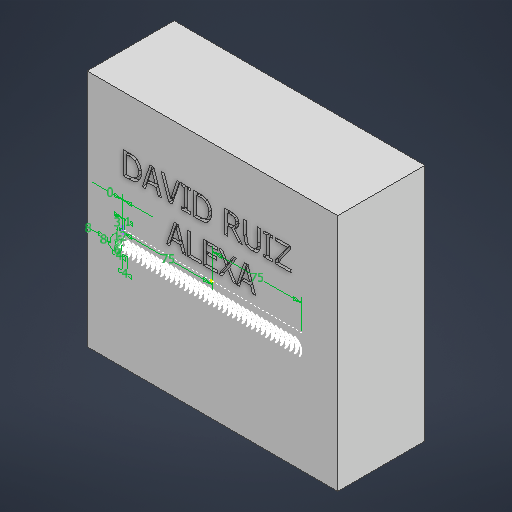
# Autodesk Inventor part: Trayectorias
Saved by Autodesk Inventor 2027.1 (Build 311270010, 270A)
## iProperties
Created: 2026-10-04
Part Number: Trayectorias
Material: Genérico
Document SubType Name: Modeling
Designer: felip
Density: 1 g/cm^3
Appearance: Valor por defecto
Author: felip
Autodesk Inventor part; units mm, degrees
ref_plane "YZ Plane" through (0, 0, 0) normal (1, 0, 0) x (0, 1, 0)
ref_plane "XZ Plane" through (0, 0, 0) normal (0, 1, 0) x (-1, 0, 0)
ref_plane "XY Plane" through (0, 0, 0) normal (0, 0, 1) x (1, 0, 0)
sketch "Boceto1" plane through (0, 0, 0) normal (0, 0, 1) x (1, 0, 0)
  line L0 (-105, 100) -> (105, 100)
  line L1 (105, 100) -> (105, -100)
  line L2 (105, -100) -> (-105, -100)
  line L3 (-105, -100) -> (-105, 100)
  line L4 (-105, 100) -> (105, -100) construction
  line L5 (105, 100) -> (-105, -100) construction
  point P0 (0, 0)
  dimension "d0" = 210
  dimension "d1" = 200
  constraints: 12 end point, 2 midpoint, 2 parallel, 1 horizontal, 1 perpendicular
  measures "d0" distance of L1.end L2.end
  measures "d1" distance of L0.end L1.end
extrude "Extrusión1" add sketch "Boceto1" along normal mid plane 73
sketch "Boceto2" plane through (0, 0, 36.5) normal (0, 0, 1) x (1, 0, 0)
  line L0 (-80.8572, 56.5825) -> (70.8243, 56.5825) construction
  line L1 (70.8243, 56.5825) -> (70.8243, 9.2236) construction
  line L2 (70.8243, 9.2236) -> (-80.8572, 9.2236) construction
  line L3 (-80.8572, 9.2236) -> (-80.8572, 56.5825) construction
  spline S0 degree 2 poles (-59.4185, 48.5703) (-59.4185, 45.9613) (-61.5335, 41.7623) (-63.3088, 40.589) knots 0 0 0 1 2 2 2
  spline S1 degree 2 poles (-63.3088, 40.589) (-64.76, 39.6782) (-67.7394, 39.0607) (-70.0551, 39.0607) knots 0 0 0 1 2 2 2
  line L4 (-70.0551, 39.0607) -> (-74.4393, 39.0607)
  line L5 (-74.4393, 39.0607) -> (-74.4393, 58.1107)
  line L6 (-74.4393, 58.1107) -> (-70.1014, 58.1107)
  spline S2 degree 2 poles (-70.1014, 58.1107) (-67.4152, 58.1107) (-64.3586, 57.308) (-63.2779, 56.5978) knots 0 0 0 1 2 2 2
  spline S3 degree 2 poles (-63.2779, 56.5978) (-61.4409, 55.3783) (-59.4185, 51.349) (-59.4185, 48.5703) knots 0 0 0 1 2 2 2
  spline S4 degree 2 poles (-62.0584, 48.6011) (-62.0584, 50.7933) (-63.5095, 53.8962) (-64.9452, 54.7762) knots 0 0 0 1 2 2 2
  spline S5 degree 2 poles (-64.9452, 54.7762) (-65.9641, 55.3783) (-68.2643, 55.9186) (-69.9779, 55.9186) knots 0 0 0 1 2 2 2
  line L7 (-69.9779, 55.9186) -> (-71.9076, 55.9186)
  line L8 (-71.9076, 55.9186) -> (-71.9076, 41.2528)
  line L9 (-71.9076, 41.2528) -> (-69.9779, 41.2528)
  spline S6 degree 2 poles (-69.9779, 41.2528) (-68.2952, 41.2528) (-65.748, 41.7932) (-64.7136, 42.5187) knots 0 0 0 1 2 2 2
  spline S7 degree 2 poles (-64.7136, 42.5187) (-63.386, 43.4141) (-62.0584, 46.3781) (-62.0584, 48.6011) knots 0 0 0 1 2 2 2
  line L10 (-58.7239, 39.0607) -> (-52.3018, 58.1107)
  line L11 (-52.3018, 58.1107) -> (-49.1834, 58.1107)
  line L12 (-49.1834, 58.1107) -> (-42.7614, 39.0607)
  line L13 (-42.7614, 39.0607) -> (-45.4321, 39.0607)
  line L14 (-45.4321, 39.0607) -> (-47.1611, 44.3867)
  line L15 (-47.1611, 44.3867) -> (-54.4322, 44.3867)
  line L16 (-54.4322, 44.3867) -> (-56.1612, 39.0607)
  line L17 (-56.1612, 39.0607) -> (-58.7239, 39.0607)
  line L18 (-47.8558, 46.5479) -> (-50.8044, 55.5172)
  line L19 (-50.8044, 55.5172) -> (-53.7375, 46.5479)
  line L20 (-53.7375, 46.5479) -> (-47.8558, 46.5479)
  line L21 (-27.1385, 58.1107) -> (-33.6995, 39.0607)
  line L22 (-33.6995, 39.0607) -> (-36.432, 39.0607)
  line L23 (-36.432, 39.0607) -> (-42.9929, 58.1107)
  line L24 (-42.9929, 58.1107) -> (-40.2759, 58.1107)
  line L25 (-40.2759, 58.1107) -> (-34.9963, 42.2872)
  line L26 (-34.9963, 42.2872) -> (-29.7166, 58.1107)
  line L27 (-29.7166, 58.1107) -> (-27.1385, 58.1107)
  line L28 (-18.6787, 39.0607) -> (-26.0579, 39.0607)
  line L29 (-26.0579, 39.0607) -> (-26.0579, 41.0058)
  line L30 (-26.0579, 41.0058) -> (-23.6342, 41.0058)
  line L31 (-23.6342, 41.0058) -> (-23.6342, 56.1656)
  line L32 (-23.6342, 56.1656) -> (-26.0579, 56.1656)
  line L33 (-26.0579, 56.1656) -> (-26.0579, 58.1107)
  line L34 (-26.0579, 58.1107) -> (-18.6787, 58.1107)
  line L35 (-18.6787, 58.1107) -> (-18.6787, 56.1656)
  line L36 (-18.6787, 56.1656) -> (-21.1024, 56.1656)
  line L37 (-21.1024, 56.1656) -> (-21.1024, 41.0058)
  line L38 (-21.1024, 41.0058) -> (-18.6787, 41.0058)
  line L39 (-18.6787, 41.0058) -> (-18.6787, 39.0607)
  spline S8 degree 2 poles (-0.5241, 48.5703) (-0.5241, 45.9613) (-2.6391, 41.7623) (-4.4144, 40.589) knots 0 0 0 1 2 2 2
  spline S9 degree 2 poles (-4.4144, 40.589) (-5.8655, 39.6782) (-8.845, 39.0607) (-11.1606, 39.0607) knots 0 0 0 1 2 2 2
  line L40 (-11.1606, 39.0607) -> (-15.5449, 39.0607)
  line L41 (-15.5449, 39.0607) -> (-15.5449, 58.1107)
  line L42 (-15.5449, 58.1107) -> (-11.2069, 58.1107)
  spline S10 degree 2 poles (-11.2069, 58.1107) (-8.5208, 58.1107) (-5.4641, 57.308) (-4.3835, 56.5978) knots 0 0 0 1 2 2 2
  spline S11 degree 2 poles (-4.3835, 56.5978) (-2.5464, 55.3783) (-0.5241, 51.349) (-0.5241, 48.5703) knots 0 0 0 1 2 2 2
  spline S12 degree 2 poles (-3.1639, 48.6011) (-3.1639, 50.7933) (-4.6151, 53.8962) (-6.0508, 54.7762) knots 0 0 0 1 2 2 2
  spline S13 degree 2 poles (-6.0508, 54.7762) (-7.0696, 55.3783) (-9.3698, 55.9186) (-11.0834, 55.9186) knots 0 0 0 1 2 2 2
  line L43 (-11.0834, 55.9186) -> (-13.0131, 55.9186)
  line L44 (-13.0131, 55.9186) -> (-13.0131, 41.2528)
  line L45 (-13.0131, 41.2528) -> (-11.0834, 41.2528)
  spline S14 degree 2 poles (-11.0834, 41.2528) (-9.4007, 41.2528) (-6.8535, 41.7932) (-5.8192, 42.5187) knots 0 0 0 1 2 2 2
  spline S15 degree 2 poles (-5.8192, 42.5187) (-4.4916, 43.4141) (-3.1639, 46.3781) (-3.1639, 48.6011) knots 0 0 0 1 2 2 2
  line L46 (25.1486, 39.0607) -> (21.8604, 39.0607)
  line L47 (21.8604, 39.0607) -> (15.8398, 46.6406)
  line L48 (15.8398, 46.6406) -> (12.9375, 46.6406)
  line L49 (12.9375, 46.6406) -> (12.9375, 39.0607)
  line L50 (12.9375, 39.0607) -> (10.4057, 39.0607)
  line L51 (10.4057, 39.0607) -> (10.4057, 58.1107)
  line L52 (10.4057, 58.1107) -> (15.3149, 58.1107)
  spline S16 degree 2 poles (15.3149, 58.1107) (16.9513, 58.1107) (19.1588, 57.7556) (20.1623, 57.1073) knots 0 0 0 1 2 2 2
  spline S17 degree 2 poles (20.1623, 57.1073) (21.1657, 56.4589) (22.3235, 54.4366) (22.3235, 52.9391) knots 0 0 0 1 2 2 2
  spline S18 degree 2 poles (22.3235, 52.9391) (22.3235, 50.855) (20.1932, 48.03) (18.3715, 47.3507) knots 0 0 0 1 2 2 2
  line L53 (18.3715, 47.3507) -> (25.1486, 39.0607)
  spline S19 degree 2 poles (19.6837, 52.7384) (19.6837, 53.5721) (19.0971, 54.8534) (18.4796, 55.2702) knots 0 0 0 1 2 2 2
  spline S20 degree 2 poles (18.4796, 55.2702) (17.9393, 55.6253) (16.5036, 55.9186) (15.4538, 55.9186) knots 0 0 0 1 2 2 2
  line L54 (15.4538, 55.9186) -> (12.9375, 55.9186)
  line L55 (12.9375, 55.9186) -> (12.9375, 48.7555)
  line L56 (12.9375, 48.7555) -> (15.1605, 48.7555)
  spline S21 degree 2 poles (15.1605, 48.7555) (16.2566, 48.7555) (18.001, 49.1415) (18.6031, 49.7435) knots 0 0 0 1 2 2 2
  spline S22 degree 2 poles (18.6031, 49.7435) (19.1588, 50.2684) (19.6837, 51.7504) (19.6837, 52.7384) knots 0 0 0 1 2 2 2
  spline S23 degree 2 poles (33.3151, 38.6593) (31.6324, 38.6593) (29.1315, 39.5393) (28.2516, 40.4192) knots 0 0 0 1 2 2 2
  spline S24 degree 2 poles (28.2516, 40.4192) (27.2481, 41.4072) (26.43, 44.186) (26.43, 46.2238) knots 0 0 0 1 2 2 2
  line L57 (26.43, 46.2238) -> (26.43, 58.1107)
  line L58 (26.43, 58.1107) -> (28.9617, 58.1107)
  line L59 (28.9617, 58.1107) -> (28.9617, 46.2238)
  spline S25 degree 2 poles (28.9617, 46.2238) (28.9617, 44.8961) (29.3013, 43.1054) (29.7799, 42.3798) knots 0 0 0 1 2 2 2
  spline S26 degree 2 poles (29.7799, 42.3798) (30.2894, 41.6079) (32.0492, 40.8206) (33.3151, 40.8206) knots 0 0 0 1 2 2 2
  spline S27 degree 2 poles (33.3151, 40.8206) (34.5038, 40.8206) (36.3563, 41.6079) (36.8658, 42.3798) knots 0 0 0 1 2 2 2
  spline S28 degree 2 poles (36.8658, 42.3798) (37.3443, 43.1054) (37.684, 44.8807) (37.684, 46.162) knots 0 0 0 1 2 2 2
  line L60 (37.684, 46.162) -> (37.684, 58.1107)
  line L61 (37.684, 58.1107) -> (40.2157, 58.1107)
  line L62 (40.2157, 58.1107) -> (40.2157, 46.2238)
  spline S29 degree 2 poles (40.2157, 46.2238) (40.2157, 44.2323) (39.413, 41.3918) (38.3941, 40.4192) knots 0 0 0 1 2 2 2
  spline S30 degree 2 poles (38.3941, 40.4192) (37.4833, 39.5238) (35.075, 38.6593) (33.3151, 38.6593) knots 0 0 0 1 2 2 2
  line L63 (50.4817, 39.0607) -> (43.1026, 39.0607)
  line L64 (43.1026, 39.0607) -> (43.1026, 41.0058)
  line L65 (43.1026, 41.0058) -> (45.5263, 41.0058)
  line L66 (45.5263, 41.0058) -> (45.5263, 56.1656)
  line L67 (45.5263, 56.1656) -> (43.1026, 56.1656)
  line L68 (43.1026, 56.1656) -> (43.1026, 58.1107)
  line L69 (43.1026, 58.1107) -> (50.4817, 58.1107)
  line L70 (50.4817, 58.1107) -> (50.4817, 56.1656)
  line L71 (50.4817, 56.1656) -> (48.058, 56.1656)
  line L72 (48.058, 56.1656) -> (48.058, 41.0058)
  line L73 (48.058, 41.0058) -> (50.4817, 41.0058)
  line L74 (50.4817, 41.0058) -> (50.4817, 39.0607)
  line L75 (65.765, 39.0607) -> (52.4577, 39.0607)
  line L76 (52.4577, 39.0607) -> (52.4577, 41.4227)
  line L77 (52.4577, 41.4227) -> (62.6466, 55.8568)
  line L78 (62.6466, 55.8568) -> (52.9209, 55.8568)
  line L79 (52.9209, 55.8568) -> (52.9209, 58.1107)
  line L80 (52.9209, 58.1107) -> (65.5025, 58.1107)
  line L81 (65.5025, 58.1107) -> (65.5025, 55.8259)
  line L82 (65.5025, 55.8259) -> (55.2056, 41.3146)
  line L83 (55.2056, 41.3146) -> (65.765, 41.3146)
  line L84 (65.765, 41.3146) -> (65.765, 39.0607)
  line L85 (-38.3539, 7.6954) -> (-31.9319, 26.7454)
  line L86 (-31.9319, 26.7454) -> (-28.8135, 26.7454)
  line L87 (-28.8135, 26.7454) -> (-22.3915, 7.6954)
  line L88 (-22.3915, 7.6954) -> (-25.0622, 7.6954)
  line L89 (-25.0622, 7.6954) -> (-26.7912, 13.0214)
  line L90 (-26.7912, 13.0214) -> (-34.0623, 13.0214)
  line L91 (-34.0623, 13.0214) -> (-35.7913, 7.6954)
  line L92 (-35.7913, 7.6954) -> (-38.3539, 7.6954)
  line L93 (-27.4859, 15.1826) -> (-30.4345, 24.1519)
  line L94 (-30.4345, 24.1519) -> (-33.3676, 15.1826)
  line L95 (-33.3676, 15.1826) -> (-27.4859, 15.1826)
  line L96 (-9.5474, 7.6954) -> (-20.5853, 7.6954)
  line L97 (-20.5853, 7.6954) -> (-20.5853, 26.7454)
  line L98 (-20.5853, 26.7454) -> (-18.0535, 26.7454)
  line L99 (-18.0535, 26.7454) -> (-18.0535, 9.9493)
  line L100 (-18.0535, 9.9493) -> (-9.5474, 9.9493)
  line L101 (-9.5474, 9.9493) -> (-9.5474, 7.6954)
  line L102 (-7.5559, 7.6954) -> (-7.5559, 26.7454)
  line L103 (-7.5559, 26.7454) -> (4.3619, 26.7454)
  line L104 (4.3619, 26.7454) -> (4.3619, 24.4915)
  line L105 (4.3619, 24.4915) -> (-5.0242, 24.4915)
  line L106 (-5.0242, 24.4915) -> (-5.0242, 19.2736)
  line L107 (-5.0242, 19.2736) -> (3.729, 19.2736)
  line L108 (3.729, 19.2736) -> (3.729, 17.0197)
  line L109 (3.729, 17.0197) -> (-5.0242, 17.0197)
  line L110 (-5.0242, 17.0197) -> (-5.0242, 9.9493)
  line L111 (-5.0242, 9.9493) -> (4.3619, 9.9493)
  line L112 (4.3619, 9.9493) -> (4.3619, 7.6954)
  line L113 (4.3619, 7.6954) -> (-7.5559, 7.6954)
  line L114 (20.3089, 7.6954) -> (17.4067, 7.6954)
  line L115 (17.4067, 7.6954) -> (12.7754, 15.2907)
  line L116 (12.7754, 15.2907) -> (8.0515, 7.6954)
  line L117 (8.0515, 7.6954) -> (5.319, 7.6954)
  line L118 (5.319, 7.6954) -> (11.386, 17.2358)
  line L119 (11.386, 17.2358) -> (5.5043, 26.7454)
  line L120 (5.5043, 26.7454) -> (8.4066, 26.7454)
  line L121 (8.4066, 26.7454) -> (12.9452, 19.289)
  line L122 (12.9452, 19.289) -> (17.5765, 26.7454)
  line L123 (17.5765, 26.7454) -> (20.3089, 26.7454)
  line L124 (20.3089, 26.7454) -> (14.35, 17.3593)
  line L125 (14.35, 17.3593) -> (20.3089, 7.6954)
  line L126 (20.2935, 7.6954) -> (26.7155, 26.7454)
  line L127 (26.7155, 26.7454) -> (29.8339, 26.7454)
  line L128 (29.8339, 26.7454) -> (36.256, 7.6954)
  line L129 (36.256, 7.6954) -> (33.5853, 7.6954)
  line L130 (33.5853, 7.6954) -> (31.8563, 13.0214)
  line L131 (31.8563, 13.0214) -> (24.5852, 13.0214)
  line L132 (24.5852, 13.0214) -> (22.8561, 7.6954)
  line L133 (22.8561, 7.6954) -> (20.2935, 7.6954)
  line L134 (31.1616, 15.1826) -> (28.213, 24.1519)
  line L135 (28.213, 24.1519) -> (25.2798, 15.1826)
  line L136 (25.2798, 15.1826) -> (31.1616, 15.1826)
  point P0 (0, 0)
  dimension "d1" = 200
  constraints: 2 other
sketch "Boceto3" plane through (0, 0, 36.5) normal (0, 0, 1) x (1, 0, 0)
  point P0 (0, 0)
sketch "Boceto4" plane through (0, 0, 36.5) normal (0, 0, 1) x (1, 0, 0)
  line L0 (0, 0) -> (-75, 0) construction
  line L1 (-75, 0) -> (-75, 0) construction
  line L2 (0, 0) -> (75, 0) construction
  ellipse E0 centre (-75, 0) end of major axis (-75, 3) minor radius 1
  line L3 (-75, 0) -> (-75, -12) construction
  arc A0 (-75, -18) -> (-75, -6) centre (-80.2915, -12) ccw
  arc A1 (-71, -18) -> (-75, -6) centre (-77.6476, -13.5492) ccw
  arc A2 (-71, -18) -> (-71, -6) centre (-76.2915, -12) ccw
  arc A3 (-67, -18) -> (-71, -6) centre (-73.6476, -13.5492) ccw
  arc A4 (-67, -18) -> (-67, -6) centre (-72.2915, -12) ccw
  arc A5 (-63, -18) -> (-67, -6) centre (-69.6476, -13.5492) ccw
  arc A6 (-63, -18) -> (-63, -6) centre (-68.2915, -12) ccw
  arc A7 (-59, -18) -> (-63, -6) centre (-65.6476, -13.5492) ccw
  arc A8 (-59, -18) -> (-59, -6) centre (-64.2915, -12) ccw
  arc A9 (-55, -18) -> (-59, -6) centre (-61.6476, -13.5492) ccw
  arc A10 (-55, -18) -> (-55, -6) centre (-60.2915, -12) ccw
  arc A11 (-51, -18) -> (-55, -6) centre (-57.6476, -13.5492) ccw
  arc A12 (-51, -18) -> (-51, -6) centre (-56.2915, -12) ccw
  arc A13 (-47, -18) -> (-51, -6) centre (-53.6476, -13.5492) ccw
  arc A14 (-47, -18) -> (-47, -6) centre (-52.2915, -12) ccw
  arc A15 (-43, -18) -> (-47, -6) centre (-49.6476, -13.5492) ccw
  arc A16 (-43, -18) -> (-43, -6) centre (-48.2915, -12) ccw
  arc A17 (-39, -18) -> (-43, -6) centre (-45.6476, -13.5492) ccw
  arc A18 (-39, -18) -> (-39, -6) centre (-44.2915, -12) ccw
  arc A19 (-35, -18) -> (-39, -6) centre (-41.6476, -13.5492) ccw
  arc A20 (-35, -18) -> (-35, -6) centre (-40.2915, -12) ccw
  arc A21 (-31, -18) -> (-35, -6) centre (-37.6476, -13.5492) ccw
  arc A22 (-31, -18) -> (-31, -6) centre (-36.2915, -12) ccw
  arc A23 (-27, -18) -> (-31, -6) centre (-33.6476, -13.5492) ccw
  arc A24 (-27, -18) -> (-27, -6) centre (-32.2915, -12) ccw
  arc A25 (-23, -18) -> (-27, -6) centre (-29.6476, -13.5492) ccw
  arc A26 (-23, -18) -> (-23, -6) centre (-28.2915, -12) ccw
  arc A27 (-19, -18) -> (-23, -6) centre (-25.6476, -13.5492) ccw
  arc A28 (-19, -18) -> (-19, -6) centre (-24.2915, -12) ccw
  arc A29 (-15, -18) -> (-19, -6) centre (-21.6476, -13.5492) ccw
  arc A30 (-15, -18) -> (-15, -6) centre (-20.2915, -12) ccw
  arc A31 (-11, -18) -> (-15, -6) centre (-17.6476, -13.5492) ccw
  arc A32 (-11, -18) -> (-11, -6) centre (-16.2915, -12) ccw
  arc A33 (-7, -18) -> (-11, -6) centre (-13.6476, -13.5492) ccw
  arc A34 (-7, -18) -> (-7, -6) centre (-12.2915, -12) ccw
  arc A35 (-3, -18) -> (-7, -6) centre (-9.6476, -13.5492) ccw
  arc A36 (-3, -18) -> (-3, -6) centre (-8.2915, -12) ccw
  arc A37 (1, -18) -> (-3, -6) centre (-5.6476, -13.5492) ccw
  arc A38 (1, -18) -> (1, -6) centre (-4.2915, -12) ccw
  arc A39 (5, -18) -> (1, -6) centre (-1.6476, -13.5492) ccw
  arc A40 (5, -18) -> (5, -6) centre (-0.2915, -12) ccw
  arc A41 (9, -18) -> (5, -6) centre (2.3524, -13.5492) ccw
  arc A42 (9, -18) -> (9, -6) centre (3.7085, -12) ccw
  arc A43 (13, -18) -> (9, -6) centre (6.3524, -13.5492) ccw
  arc A44 (13, -18) -> (13, -6) centre (7.7085, -12) ccw
  arc A45 (17, -18) -> (13, -6) centre (10.3524, -13.5492) ccw
  arc A46 (17, -18) -> (17, -6) centre (11.7085, -12) ccw
  arc A47 (21, -18) -> (17, -6) centre (14.3524, -13.5492) ccw
  arc A48 (21, -18) -> (21, -6) centre (15.7085, -12) ccw
  arc A49 (25, -18) -> (21, -6) centre (18.3524, -13.5492) ccw
  arc A50 (25, -18) -> (25, -6) centre (19.7085, -12) ccw
  arc A51 (29, -18) -> (25, -6) centre (22.3524, -13.5492) ccw
  arc A52 (29, -18) -> (29, -6) centre (23.7085, -12) ccw
  arc A53 (33, -18) -> (29, -6) centre (26.3524, -13.5492) ccw
  arc A54 (33, -18) -> (33, -6) centre (27.7085, -12) ccw
  arc A55 (37, -18) -> (33, -6) centre (30.3524, -13.5492) ccw
  arc A56 (37, -18) -> (37, -6) centre (31.7085, -12) ccw
  arc A57 (41, -18) -> (37, -6) centre (34.3524, -13.5492) ccw
  arc A58 (41, -18) -> (41, -6) centre (35.7085, -12) ccw
  arc A59 (45, -18) -> (41, -6) centre (38.3524, -13.5492) ccw
  arc A60 (45, -18) -> (45, -6) centre (39.7085, -12) ccw
  arc A61 (49, -18) -> (45, -6) centre (42.3524, -13.5492) ccw
  arc A62 (49, -18) -> (49, -6) centre (43.7085, -12) ccw
  arc A63 (53, -18) -> (49, -6) centre (46.3524, -13.5492) ccw
  arc A64 (53, -18) -> (53, -6) centre (47.7085, -12) ccw
  arc A65 (57, -18) -> (53, -6) centre (50.3524, -13.5492) ccw
  arc A66 (57, -18) -> (57, -6) centre (51.7085, -12) ccw
  arc A67 (61, -18) -> (57, -6) centre (54.3524, -13.5492) ccw
  arc A68 (61, -18) -> (61, -6) centre (55.7085, -12) ccw
  arc A69 (65, -18) -> (61, -6) centre (58.3524, -13.5492) ccw
  arc A70 (65, -18) -> (65, -6) centre (59.7085, -12) ccw
  arc A71 (69, -18) -> (65, -6) centre (62.3524, -13.5492) ccw
  arc A72 (69, -18) -> (69, -6) centre (63.7085, -12) ccw
  arc A73 (73, -18) -> (69, -6) centre (66.3524, -13.5492) ccw
  dimension "d7" = 1
  dimension "d8" = 3
  dimension "d4" = 75
  dimension "d5" = 0
  dimension "d6" = 75
  dimension "d16" = 12
  dimension "d25" = 4
  dimension "d34" = 6
  dimension "d38" = 6
  dimension "d39" = 6
  dimension "d40" = 8
  dimension "d42" = 4
  dimension "d43" = 8
  constraints: 148 point on circle, 74 centre point, 8 end point, 3 horizontal, 2 point on line, 1 coincident, 1 midpoint, 1 perpendicular, 254 other
  measures "d4" distance of L0.start L0.end
  measures "d5" distance of L0.end L1.end
  measures "d6" distance of L0.start L2.end
  measures "d16" distance of L3.start L3.end
  measures "d25" distance of A0.centre A2.centre
  measures "d34" distance of A0.end L3.end
  measures "d38" distance of A0.start L3.end
  measures "d39" vertical distance of A1.start L3.end
  measures "d40" radius of A0
  measures "d42" distance of A1.start A0.start
  measures "d43" radius of A1
emboss "Repujado1" sketch "Boceto2" operation cut depth 3 direction (0, 0, -1)
